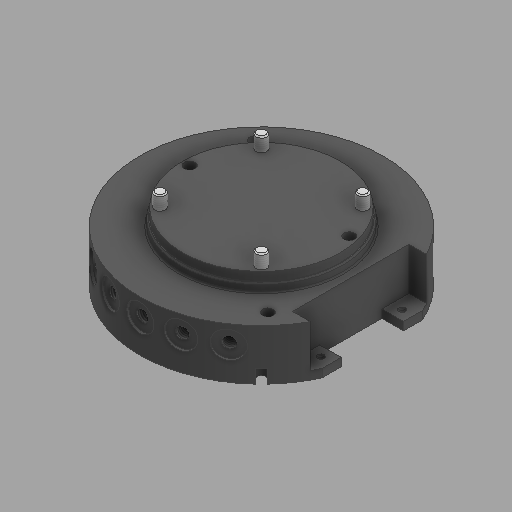
# Autodesk Inventor part: SCHUNK-SWK-020, 0
Saved by Autodesk Inventor 2025.3 (Build 293356000, 356)
## iProperties
Category: PARTsolutions
Company: SCHUNK
Created: 2026-08-11
Part Number: SCHUNK-SWK-020, 0
Material: Generic
Catalog Web Link: www.3dfindit.com
Description: SWS-Quick change system
Vendor: SCHUNK
Document SubType Name: Modeling
Designer: psAdmin
Manufacturer: SCHUNK
Mass: 134.925 g
Surface Area: 279.959 cm^2
Volume: 134.925 cm^3
Density: 1 g/cm^3
Appearance: PSOLRGB-84-84-84
PSOL_IDENT_0: {$CADENAS_DATA/23d-libs/schunk/greifsysteme/roboterzubehoer/wechseln/schnellwechselsystem/sws/sws.pr
PSOL_IDENT_1: j},171 {VTYP=3D},{NB=SCHUNK-SWK-020, 0},{LINA=SCHUNK-SWK-020},{NN=SWS},{DATE=18.09.2025 11:03:47},{G
PSOL_IDENT_2: EOMDATE=08.07.2025 10:05:37},{VERSION=},{LINEID=70},{WBVAR=SIP},{WBNUMERIC=}  {NB=SCHUNK-SWK-020, 0}
PSOL_IDENT_3: ,{LINA=SCHUNK-SWK-020},{KT=7},{TYP=SWK-020},{ABDECK=1.000},{TYP1=5.000},{NHS=0.000},{ONLINE=Zur Prod
PSOL_IDENT_4: uktseite},{SIP=ohne},{TYPSIP='ohne','ohne','SWK-020-SIP','0302325 - SWK-020-SIP'},{NBSIP=0},{SWSI=1.
PSOL_IDENT_5: 000},{PARTSERVER=0.000},{V=7.000},{SWKH=1.000},{L1=86.000},{L2=23.000},{L3=0.000},{L3A=0.000},{L4=0.
PSOL_IDENT_6: 000},{L4A=0.000},{L5=0.000},{L5A=0.000},{L6=14.000},{L6A=3.200},{L7=5.700},{L8=0.500},{L9=30.000},{L
PSOL_IDENT_7: 10=43.000},{L11=0.000},{B1=18.700},{B2=3.000},{B3=12.000},{B3A=0.000},{B4=8.300},{B4I=38.600},{B5=32
PSOL_IDENT_8: .000},{B5A=0.000},{B6=33.000},{B7=26.500},{B8=0.000},{B9=0.000},{B9A=0.000},{B9B=0.000},{B9C=0.000},
PSOL_IDENT_9: {B10=58.400},{B11=4.000},{B12=41.000},{B13=3.000},{B14=0.000},{A=13.600},{D1=60.000},{D2=90.000},{D3=
PSOL_IDENT_10: 53.000},{D4=4.000},{D5=0.000},{D6=4.000},{W1=0.000},{W1A=0.000},{W2=17.000},{W3=45.000},{W4=45.000},
PSOL_IDENT_11: {W5=15.000},{W6=0.000},{W7=0.000},{W8=0.000},{T1=4.000},{T2=7.000},{T2A=0.000},{T3=7.000},{T4=0.000}
PSOL_IDENT_12: ,{T5=0.000},{T6=16.000},{T7=0.000},{M1=M4},{NDR1=4.000},{KDR1=3.141},{M2=M5},{NDR2=5.000},{KDR2=4.13
PSOL_IDENT_13: 4},{M2A=-},{NDR2A=0.000},{KDR2A=0.000},{M3=M5},{NDR3=5.000},{KDR3=4.134},{M4=-},{NDR4=0.000},{KDR4=0
PSOL_IDENT_14: .000},{M5=M3},{NDR5=3.000},{KDR5=2.459},{M6=-},{NDR6=0.000},{KDR6=0.000},{B=38.800},{C=7.050},{D=9.5
PSOL_IDENT_15: 00},{E=10.000},{F=9.000},{G=4.000},{H=1.000},{R=2.000},{YX=33.000},{SWSI1=5.000},{CUSTOM=SWK-020_SCH
PSOL_IDENT_16: UNK},{SCHSWS=2.000},{G1=0.000},{PY1=0.000},{PX1=0.000},{BG=020}
NB: SCHUNK-SWK-020, 0
NN: SWS
NT: Quick change system
NBSYN: SCHUNK-$TYP., $NBSIP.
LINA: SCHUNK-SWK-020
CATALOG: SCHUNK
TYP: SWK-020
NHS: 0
ONLINE: To the product page
SIP: without
CUSTOM: SWK-020_SCHUNK
SUPPLIER: SCHUNK
ARTICLENO: SCHUNK-SWK-020, 0
BOMINFO: SCHUNK-SWK-020
CREATOR: CADENAS GmbH
Title: SCHUNK-SWK-020
Author: Cadenas PARTsolutions
Comments: Quick change system
Autodesk Inventor part; units mm, degrees
sketch "Sketch_1" plane through (0, 0, 0) normal (0, 0, 1) x (1, 0, 0)
  line L0 (0, -0.2) -> (0, 17.8)
  line L1 (0, 17.8) -> (19, 17.8)
  line L2 (19, 17.8) -> (19, 21.7)
  line L3 (19, 21.7) -> (21.5, 21.7)
  line L4 (21.5, 21.7) -> (21.5, 20.7)
  line L5 (21.5, 20.7) -> (23.75, 20.7)
  line L6 (23.75, 20.7) -> (23.75, 21.7)
  line L7 (23.75, 21.7) -> (29.5, 21.7)
  line L8 (29.5, 21.7) -> (30, 21.2)
  line L9 (30, 21.2) -> (30, 19.2)
  arc A0 (30, 19.2) -> (30.5, 18.7) centre (30.5, 19.2) ccw
  line L10 (30.5, 18.7) -> (45, 18.7)
  line L11 (45, 18.7) -> (45, 0)
  line L12 (45, 0) -> (31, 0)
  line L13 (31, 0) -> (31, -0.2)
  line L14 (31, -0.2) -> (19.4, -0.2)
  line L15 (19.4, -0.2) -> (19.4, -11.6)
  line L16 (19.4, -11.6) -> (17.4, -13.6)
  line L17 (17.4, -13.6) -> (13.27, -13.6)
  line L18 (13.27, -13.6) -> (13.27, -0.2)
  line L19 (13.27, -0.2) -> (0, -0.2)
  line L20 (0, -0.2) -> (0, 17.8)
  constraints: 42 end point, 2 point on circle, 1 centre point
revolve "Revolution1" add sketch "Sketch_1" angle 360 about axis through (0, -0.2, 0) along (0, 1, 0)
sketch "Sketch_5" plane through (0, -7.1, 0) normal (0, 1, 0) x (1, 0, 0)
  line L0 (-15.6, 4.8) -> (-15.6, -4.8)
  arc A0 (-15.6, 4.8) -> (-15.6, -4.8) centre (-15.6, 0) ccw
  line L1 (-15.6, 4.8) -> (-15.6, -4.8)
  constraints: 4 end point, 2 point on circle, 1 centre point
revolve "Revolution2" cut sketch "Sketch_5" angle 360 about axis through (-15.6, -7.1, -4.8) along (0, 0, -1)
sketch "Sketch_36" plane through (0, -7.1, 0) normal (0, 1, 0) x (1, 0, 0)
  line L0 (-15.6, 4.8) -> (-15.6, -4.8)
  arc A0 (-15.6, 4.8) -> (-15.6, -4.8) centre (-15.6, 0) ccw
  line L1 (-15.6, 4.8) -> (-15.6, -4.8)
  constraints: 4 end point, 2 point on circle, 1 centre point
revolve "Revolution3" add sketch "Sketch_36" angle 360 about axis through (-15.6, -7.1, -4.8) along (0, 0, -1)
sketch "Sketch_3" plane through (0, -7.1, 0) normal (0, 1, 0) x (1, 0, 0)
  line L0 (4.8, 15.6) -> (-4.8, 15.6)
  arc A0 (4.8, 15.6) -> (-4.8, 15.6) centre (0, 15.6) ccw
  line L1 (4.8, 15.6) -> (-4.8, 15.6)
  constraints: 4 end point, 2 point on circle, 1 centre point
revolve "Revolution4" cut sketch "Sketch_3" angle 360 about axis through (4.8, -7.1, -15.6) along (1, 0, 0)
sketch "Sketch_6" plane through (0, -7.1, 0) normal (0, 1, 0) x (1, 0, 0)
  line L0 (4.8, 15.6) -> (-4.8, 15.6)
  arc A0 (4.8, 15.6) -> (-4.8, 15.6) centre (0, 15.6) ccw
  line L1 (4.8, 15.6) -> (-4.8, 15.6)
  constraints: 4 end point, 2 point on circle, 1 centre point
revolve "Revolution5" add sketch "Sketch_6" angle 360 about axis through (4.8, -7.1, -15.6) along (1, 0, 0)
sketch "Sketch_4" plane through (0, -7.1, 0) normal (0, 1, 0) x (1, 0, 0)
  line L0 (-4.8, -15.6) -> (4.8, -15.6)
  arc A0 (-4.8, -15.6) -> (4.8, -15.6) centre (0, -15.6) ccw
  line L1 (-4.8, -15.6) -> (4.8, -15.6)
  constraints: 4 end point, 2 point on circle, 1 centre point
revolve "Revolution6" cut sketch "Sketch_4" angle 360 about axis through (-4.8, -7.1, 15.6) along (-1, 0, 0)
sketch "Sketch_7" plane through (0, -7.1, 0) normal (0, 1, 0) x (1, 0, 0)
  line L0 (-4.8, -15.6) -> (4.8, -15.6)
  arc A0 (-4.8, -15.6) -> (4.8, -15.6) centre (0, -15.6) ccw
  line L1 (-4.8, -15.6) -> (4.8, -15.6)
  constraints: 4 end point, 2 point on circle, 1 centre point
revolve "Revolution7" add sketch "Sketch_7" angle 360 about axis through (-4.8, -7.1, 15.6) along (-1, 0, 0)
sketch "Sketch_2" plane through (0, -7.1, 0) normal (0, 1, 0) x (1, 0, 0)
  line L0 (15.6, -4.8) -> (15.6, 4.8)
  arc A0 (15.6, -4.8) -> (15.6, 4.8) centre (15.6, 0) ccw
  line L1 (15.6, -4.8) -> (15.6, 4.8)
  constraints: 4 end point, 2 point on circle, 1 centre point
revolve "Revolution8" cut sketch "Sketch_2" angle 360 about axis through (15.6, -7.1, 4.8) along (0, 0, 1)
sketch "Sketch_8" plane through (0, -7.1, 0) normal (0, 1, 0) x (1, 0, 0)
  line L0 (15.6, -4.8) -> (15.6, 4.8)
  arc A0 (15.6, -4.8) -> (15.6, 4.8) centre (15.6, 0) ccw
  line L1 (15.6, -4.8) -> (15.6, 4.8)
  constraints: 4 end point, 2 point on circle, 1 centre point
revolve "Revolution9" add sketch "Sketch_8" angle 360 about axis through (15.6, -7.1, 4.8) along (0, 0, 1)
sketch "Sketch_12" plane through (0, 0, 18.7383) normal (0, 0, 1) x (1, 0, 0)
  line L0 (18.7383, -0.2) -> (18.7383, 0.7)
  line L1 (18.7383, 0.7) -> (22.6883, 0.7)
  line L2 (22.6883, 0.7) -> (23.5883, -0.2)
  line L3 (23.5883, -0.2) -> (18.7383, -0.2)
  line L4 (18.7383, -0.2) -> (18.7383, 0.7)
  constraints: 10 end point
revolve "Revolution10" cut sketch "Sketch_12" angle 360 about axis through (18.7383, -0.2, 18.7383) along (0, 1, 0)
sketch "Sketch_13" plane through (0, 0, 18.7383) normal (0, 0, 1) x (1, 0, 0)
  line L0 (-18.7383, -0.2) -> (-18.7383, 0.7)
  line L1 (-18.7383, 0.7) -> (-14.7883, 0.7)
  line L2 (-14.7883, 0.7) -> (-13.8883, -0.2)
  line L3 (-13.8883, -0.2) -> (-18.7383, -0.2)
  line L4 (-18.7383, -0.2) -> (-18.7383, 0.7)
  constraints: 10 end point
revolve "Revolution11" cut sketch "Sketch_13" angle 360 about axis through (-18.7383, -0.2, 18.7383) along (0, 1, 0)
sketch "Sketch_14" plane through (0, 0, -18.7383) normal (0, 0, 1) x (1, 0, 0)
  line L0 (18.7383, -0.2) -> (18.7383, 0.7)
  line L1 (18.7383, 0.7) -> (22.6883, 0.7)
  line L2 (22.6883, 0.7) -> (23.5883, -0.2)
  line L3 (23.5883, -0.2) -> (18.7383, -0.2)
  line L4 (18.7383, -0.2) -> (18.7383, 0.7)
  constraints: 10 end point
revolve "Revolution12" cut sketch "Sketch_14" angle 360 about axis through (18.7383, -0.2, -18.7383) along (0, 1, 0)
sketch "Sketch_15" plane through (0, 0, -18.7383) normal (0, 0, 1) x (1, 0, 0)
  line L0 (-18.7383, -0.2) -> (-18.7383, 0.7)
  line L1 (-18.7383, 0.7) -> (-14.7883, 0.7)
  line L2 (-14.7883, 0.7) -> (-13.8883, -0.2)
  line L3 (-13.8883, -0.2) -> (-18.7383, -0.2)
  line L4 (-18.7383, -0.2) -> (-18.7383, 0.7)
  constraints: 10 end point
revolve "Revolution13" cut sketch "Sketch_15" angle 360 about axis through (-18.7383, -0.2, -18.7383) along (0, 1, 0)
sketch "Sketch_10" plane through (0, 0, 0) normal (0, 0, 1) x (1, 0, 0)
  line L0 (0, 21.7) -> (0, 24.9)
  line L1 (0, 24.9) -> (29.2, 24.9)
  line L2 (29.2, 24.9) -> (29.2, 21.7)
  line L3 (29.2, 21.7) -> (0, 21.7)
  line L4 (0, 21.7) -> (0, 24.9)
  constraints: 10 end point
revolve "Revolution14" add sketch "Sketch_10" angle 360 about axis through (0, 21.7, 0) along (0, -1, 0)
sketch "Sketch_16" plane through (0, 0, 18.7383) normal (0, 0, 1) x (1, 0, 0)
  line L0 (18.7383, 21.7) -> (18.7383, 30)
  line L1 (18.7383, 30) -> (20.3088, 30)
  line L2 (20.3088, 30) -> (20.7383, 29.5705)
  line L3 (20.7383, 29.5705) -> (20.7383, 21.7)
  line L4 (20.7383, 21.7) -> (18.7383, 21.7)
  line L5 (18.7383, 21.7) -> (18.7383, 30)
  constraints: 12 end point
revolve "Revolution15" add sketch "Sketch_16" angle 360 about axis through (18.7383, 21.7, 18.7383) along (0, 1, 0)
thread "Thread1" size "M4x0.7" class "6g" standard "ISO Metric profile" length 7.8705
sketch "Sketch_17" plane through (0, 0, 18.7383) normal (0, 0, 1) x (1, 0, 0)
  line L0 (-18.7383, 21.7) -> (-18.7383, 30)
  line L1 (-18.7383, 30) -> (-17.1678, 30)
  line L2 (-17.1678, 30) -> (-16.7383, 29.5705)
  line L3 (-16.7383, 29.5705) -> (-16.7383, 21.7)
  line L4 (-16.7383, 21.7) -> (-18.7383, 21.7)
  line L5 (-18.7383, 21.7) -> (-18.7383, 30)
  constraints: 12 end point
revolve "Revolution16" add sketch "Sketch_17" angle 360 about axis through (-18.7383, 21.7, 18.7383) along (0, 1, 0)
thread "Thread2" size "M4x0.7" class "6g" standard "ISO Metric profile" length 7.8705
sketch "Sketch_18" plane through (0, 0, -18.7383) normal (0, 0, 1) x (1, 0, 0)
  line L0 (18.7383, 21.7) -> (18.7383, 30)
  line L1 (18.7383, 30) -> (20.3088, 30)
  line L2 (20.3088, 30) -> (20.7383, 29.5705)
  line L3 (20.7383, 29.5705) -> (20.7383, 21.7)
  line L4 (20.7383, 21.7) -> (18.7383, 21.7)
  line L5 (18.7383, 21.7) -> (18.7383, 30)
  constraints: 12 end point
revolve "Revolution17" add sketch "Sketch_18" angle 360 about axis through (18.7383, 21.7, -18.7383) along (0, 1, 0)
thread "Thread3" size "M4x0.7" class "6g" standard "ISO Metric profile" length 7.8705
sketch "Sketch_19" plane through (0, 0, -18.7383) normal (0, 0, 1) x (1, 0, 0)
  line L0 (-18.7383, 21.7) -> (-18.7383, 30)
  line L1 (-18.7383, 30) -> (-17.1678, 30)
  line L2 (-17.1678, 30) -> (-16.7383, 29.5705)
  line L3 (-16.7383, 29.5705) -> (-16.7383, 21.7)
  line L4 (-16.7383, 21.7) -> (-18.7383, 21.7)
  line L5 (-18.7383, 21.7) -> (-18.7383, 30)
  constraints: 12 end point
revolve "Revolution18" add sketch "Sketch_19" angle 360 about axis through (-18.7383, 21.7, -18.7383) along (0, 1, 0)
thread "Thread4" size "M4x0.7" class "6g" standard "ISO Metric profile" length 7.8705
sketch "Sketch_20" plane through (45, 0, 0) normal (1, 0, 0) x (0, 0, -1)
  line L0 (-21.5, 2.999) -> (-11.5, 2.999)
  line L1 (-11.5, 2.999) -> (-11.5, -0.001)
  line L2 (-11.5, -0.001) -> (11.5, -0.001)
  line L3 (11.5, -0.001) -> (11.5, 2.999)
  line L4 (11.5, 2.999) -> (21.5, 2.999)
  line L5 (21.5, 2.999) -> (21.5, 18.701)
  line L6 (21.5, 18.701) -> (-21.5, 18.701)
  line L7 (-21.5, 18.701) -> (-21.5, 2.999)
  constraints: 16 end point
extrude "Extrusion1" cut sketch "Sketch_20" against normal blind 12
sketch "Sketch20" plane through (33, 0, -11.5) normal (0, -1, 0) x (1, 0, 0)
  point P0 (-67.9051, 0.8284)
hole "Hole1" at (-34.9051, 0, -10.6716) direction (0, 1, 0) diameter 3 depth 7.05 tip angle 120 countersink diameter 8 countersink angle 90
sketch "Sketch21" plane through (33, 0, -11.5) normal (0, -1, 0) x (1, 0, 0)
  point P0 (-67.9051, 22.1716)
hole "Hole2" at (-34.9051, 0, 10.6716) direction (0, 1, 0) diameter 3 depth 7.05 tip angle 120 countersink diameter 8 countersink angle 90
sketch "Sketch22" plane through (33, 0, -11.5) normal (0, -1, 0) x (1, 0, 0)
  point P0 (-63.2599, -8.9105)
hole "Hole3" at (-30.2599, 0, -20.4105) direction (0, 1, 0) diameter 3 depth 7.05 tip angle 120 countersink diameter 8 countersink angle 90
sketch "Sketch23" plane through (33, 0, -11.5) normal (0, -1, 0) x (1, 0, 0)
  point P0 (-63.2599, 31.9105)
hole "Hole4" at (-30.2599, 0, 20.4105) direction (0, 1, 0) diameter 3 depth 7.05 tip angle 120 countersink diameter 8 countersink angle 90
sketch "Sketch24" plane through (33, 0, -11.5) normal (0, -1, 0) x (1, 0, 0)
  point P0 (-22.3284, 46.4051)
hole "Hole5" at (10.6716, 0, 34.9051) direction (0, 1, 0) diameter 3 depth 7.05 tip angle 120 countersink diameter 8 countersink angle 90
sketch "Sketch25" plane through (33, 0, -11.5) normal (0, -1, 0) x (1, 0, 0)
  point P0 (-43.6716, 46.4051)
hole "Hole6" at (-10.6716, 0, 34.9051) direction (0, 1, 0) diameter 3 depth 7.05 tip angle 120 countersink diameter 8 countersink angle 90
sketch "Sketch26" plane through (33, 0, -11.5) normal (0, -1, 0) x (1, 0, 0)
  point P0 (-12.5895, 41.7599)
hole "Hole7" at (20.4105, 0, 30.2599) direction (0, 1, 0) diameter 3 depth 7.05 tip angle 120 countersink diameter 8 countersink angle 90
sketch "Sketch27" plane through (33, 0, -11.5) normal (0, -1, 0) x (1, 0, 0)
  point P0 (-53.4105, 41.7599)
hole "Hole8" at (-20.4105, 0, 30.2599) direction (0, 1, 0) diameter 3 depth 7.05 tip angle 120 countersink diameter 8 countersink angle 90
sketch "Sketch28" plane through (33, 0, -11.5) normal (0, -1, 0) x (1, 0, 0)
  point P0 (-12.5895, -18.7599)
hole "Hole9" at (20.4105, 0, -30.2599) direction (0, 1, 0) diameter 3 depth 7.05 tip angle 120 countersink diameter 8 countersink angle 90
sketch "Sketch29" plane through (33, 0, -11.5) normal (0, -1, 0) x (1, 0, 0)
  point P0 (-53.4105, -18.7599)
hole "Hole10" at (-20.4105, 0, -30.2599) direction (0, 1, 0) diameter 3 depth 7.05 tip angle 120 countersink diameter 8 countersink angle 90
sketch "Sketch30" plane through (33, 0, -11.5) normal (0, -1, 0) x (1, 0, 0)
  point P0 (-22.3284, -23.4051)
hole "Hole11" at (10.6716, 0, -34.9051) direction (0, 1, 0) diameter 3 depth 7.05 tip angle 120 countersink diameter 8 countersink angle 90
sketch "Sketch31" plane through (33, 0, -11.5) normal (0, -1, 0) x (1, 0, 0)
  point P0 (-43.6716, -23.4051)
hole "Hole12" at (-10.6716, 0, -34.9051) direction (0, 1, 0) diameter 3 depth 7.05 tip angle 120 countersink diameter 8 countersink angle 90
sketch "Sketch_33" plane through (0, 0, 0) normal (1, 0, 0) x (0, 1, 0)
  line L0 (-9.199, -26) -> (-0.199, -26)
  line L1 (-0.199, -26) -> (-0.199, -28)
  line L2 (-0.199, -28) -> (-1.199, -28)
  line L3 (-1.199, -28) -> (-8.323, -27.1095)
  arc A0 (-9.199, -26.1172) -> (-8.323, -27.1095) centre (-8.199, -26.1172) ccw
  line L4 (-9.199, -26.1172) -> (-9.199, -26)
  line L5 (-9.199, -26) -> (-0.199, -26)
  constraints: 12 end point, 2 point on circle, 1 centre point
revolve "Revolution19" add sketch "Sketch_33" angle 360 about axis through (0, -9.199, -26) along (0, 1, 0)
sketch "Sketch_37" plane through (0, 0, -6.8587) normal (0, 0, 1) x (1, 0, 0)
  line L0 (-25.597, 3.3) -> (-25.597, -0.2)
  line L1 (-25.597, -0.2) -> (-28.597, -0.2)
  line L2 (-28.597, -0.2) -> (-28.597, 3.3)
  line L3 (-28.597, 3.3) -> (-25.597, 3.3)
  line L4 (-25.597, 3.3) -> (-25.597, -0.2)
  constraints: 10 end point
revolve "Revolution20" cut sketch "Sketch_37" angle 360 about axis through (-25.597, 3.3, -6.8587) along (0, -1, 0)
sketch "Sketch_38" plane through (0, 0, 6.8587) normal (0, 0, 1) x (1, 0, 0)
  line L0 (25.597, 3.3) -> (25.597, -0.2)
  line L1 (25.597, -0.2) -> (22.597, -0.2)
  line L2 (22.597, -0.2) -> (22.597, 3.3)
  line L3 (22.597, 3.3) -> (25.597, 3.3)
  line L4 (25.597, 3.3) -> (25.597, -0.2)
  constraints: 10 end point
revolve "Revolution21" cut sketch "Sketch_38" angle 360 about axis through (25.597, 3.3, 6.8587) along (0, -1, 0)
sketch "Sketch_39" plane through (0, -0.001, 0) normal (0, 1, 0) x (1, 0, 0)
  line L0 (41, -25) -> (46, -25)
  line L1 (46, -25) -> (46, 25)
  line L2 (46, 25) -> (41, 25)
  line L3 (41, 25) -> (41, -25)
  constraints: 8 end point
extrude "Extrusion2" cut sketch "Sketch_39" along normal blind 4
sketch "Sketch_40" plane through (37, 0, 0) normal (1, 0, 0) x (0, 0, -1)
  line L0 (15, 0) -> (15, 3)
  line L1 (15, 3) -> (16.2295, 3)
  line L2 (16.2295, 3) -> (16.2295, 0)
  line L3 (16.2295, 0) -> (15, 0)
  line L4 (15, 0) -> (15, 3)
  constraints: 10 end point
revolve "Revolution22" cut sketch "Sketch_40" angle 360 about axis through (37, 0, -15) along (0, 1, 0)
thread "Thread5" size "M3x0.5" class "6H" standard "ISO Metric profile" length 3
sketch "Sketch_41" plane through (37, 0, 0) normal (1, 0, 0) x (0, 0, -1)
  line L0 (-15, 0) -> (-15, 3)
  line L1 (-15, 3) -> (-13.7705, 3)
  line L2 (-13.7705, 3) -> (-13.7705, 0)
  line L3 (-13.7705, 0) -> (-15, 0)
  line L4 (-15, 0) -> (-15, 3)
  constraints: 10 end point
revolve "Revolution23" cut sketch "Sketch_41" angle 360 about axis through (37, 0, 15) along (0, 1, 0)
thread "Thread6" size "M3x0.5" class "6H" standard "ISO Metric profile" length 3
sketch "Sketch_42" plane through (0, -0.001, 0) normal (0, 1, 0) x (1, 0, 0)
  arc A0 (31.1127, -28.9914) -> (28.9914, -31.1127) centre (30.052, -30.052) ccw
  line L0 (28.9914, -31.1127) -> (30.7591, -32.8805)
  line L1 (30.7591, -32.8805) -> (32.8805, -30.7591)
  line L2 (32.8805, -30.7591) -> (31.1127, -28.9914)
  constraints: 6 end point, 2 point on circle, 1 centre point
extrude "Extrusion3" cut sketch "Sketch_42" along normal blind 5
sketch "Sketch_43" plane through (0, -0.001, 0) normal (0, 1, 0) x (1, 0, 0)
  line L0 (-32.8805, -30.7591) -> (-30.7591, -32.8805)
  line L1 (-30.7591, -32.8805) -> (-28.9914, -31.1127)
  arc A0 (-28.9914, -31.1127) -> (-31.1127, -28.9914) centre (-30.052, -30.052) ccw
  line L2 (-31.1127, -28.9914) -> (-32.8805, -30.7591)
  constraints: 6 end point, 2 point on circle, 1 centre point
extrude "Extrusion4" cut sketch "Sketch_43" along normal blind 5
sketch "Sketch_44" plane through (0, 12, 0) normal (0, 1, 0) x (1, 0, 0)
  line L0 (13.1567, -43.0337) -> (9.5186, -31.1341)
  line L1 (9.5186, -31.1341) -> (11.8442, -31.671)
  line L2 (11.8442, -31.671) -> (14.841, -41.4731)
  line L3 (14.841, -41.4731) -> (17.6459, -40.6156)
  line L4 (17.6459, -40.6156) -> (17.9383, -41.5719)
  line L5 (17.9383, -41.5719) -> (13.1567, -43.0337)
  line L6 (13.1567, -43.0337) -> (9.5186, -31.1341)
  constraints: 14 end point
revolve "Revolution24" cut sketch "Sketch_44" angle 360 about axis through (13.1567, 12, 43.0337) along (-0.2923717, 0, -0.9563048)
thread "Thread7" size "M5x0.8" class "6H" standard "ISO Metric profile" length 7
sketch "Sketch_45" plane through (0, 12, 0) normal (0, 1, 0) x (1, 0, 0)
  line L0 (25.1637, -37.3067) -> (18.2054, -26.9907)
  line L1 (18.2054, -26.9907) -> (20.5864, -26.8242)
  line L2 (20.5864, -26.8242) -> (26.3181, -35.3218)
  line L3 (26.3181, -35.3218) -> (28.7497, -33.6817)
  line L4 (28.7497, -33.6817) -> (29.3089, -34.5107)
  line L5 (29.3089, -34.5107) -> (25.1637, -37.3067)
  line L6 (25.1637, -37.3067) -> (18.2054, -26.9907)
  constraints: 14 end point
revolve "Revolution25" cut sketch "Sketch_45" angle 360 about axis through (25.1637, 12, 37.3067) along (-0.5591929, 0, -0.8290376)
thread "Thread8" size "M5x0.8" class "6H" standard "ISO Metric profile" length 7
sketch "Sketch_46" plane through (0, 12, 0) normal (0, 1, 0) x (1, 0, 0)
  line L0 (-13.1567, -43.0337) -> (-9.5186, -31.1341)
  line L1 (-9.5186, -31.1341) -> (-7.8909, -32.8796)
  line L2 (-7.8909, -32.8796) -> (-10.8877, -42.6817)
  line L3 (-10.8877, -42.6817) -> (-8.0828, -43.5393)
  line L4 (-8.0828, -43.5393) -> (-8.3752, -44.4956)
  line L5 (-8.3752, -44.4956) -> (-13.1567, -43.0337)
  line L6 (-13.1567, -43.0337) -> (-9.5186, -31.1341)
  constraints: 14 end point
revolve "Revolution26" cut sketch "Sketch_46" angle 360 about axis through (-13.1567, 12, 43.0337) along (0.2923717, 0, -0.9563048)
thread "Thread9" size "M5x0.8" class "6H" standard "ISO Metric profile" length 7
sketch "Sketch_47" plane through (0, 12, 0) normal (0, 1, 0) x (1, 0, 0)
  line L0 (-25.1637, -37.3067) -> (-18.2054, -26.9907)
  line L1 (-18.2054, -26.9907) -> (-17.1591, -29.1359)
  line L2 (-17.1591, -29.1359) -> (-22.8909, -37.6335)
  line L3 (-22.8909, -37.6335) -> (-20.4593, -39.2736)
  line L4 (-20.4593, -39.2736) -> (-21.0185, -40.1027)
  line L5 (-21.0185, -40.1027) -> (-25.1637, -37.3067)
  line L6 (-25.1637, -37.3067) -> (-18.2054, -26.9907)
  constraints: 14 end point
revolve "Revolution27" cut sketch "Sketch_47" angle 360 about axis through (-25.1637, 12, 37.3067) along (0.5591929, 0, -0.8290376)
thread "Thread10" size "M5x0.8" class "6H" standard "ISO Metric profile" length 7
sketch "Sketch_48" plane through (0, 12, 0) normal (0, 1, 0) x (1, 0, 0)
  line L0 (-43.0337, -13.1567) -> (-31.1341, -9.5186)
  line L1 (-31.1341, -9.5186) -> (-31.671, -11.8442)
  line L2 (-31.671, -11.8442) -> (-41.4731, -14.841)
  line L3 (-41.4731, -14.841) -> (-40.6156, -17.6459)
  line L4 (-40.6156, -17.6459) -> (-41.5719, -17.9383)
  line L5 (-41.5719, -17.9383) -> (-43.0337, -13.1567)
  line L6 (-43.0337, -13.1567) -> (-31.1341, -9.5186)
  constraints: 14 end point
revolve "Revolution28" cut sketch "Sketch_48" angle 360 about axis through (-43.0337, 12, 13.1567) along (0.9563048, 0, -0.2923717)
thread "Thread11" size "M5x0.8" class "6H" standard "ISO Metric profile" length 7
sketch "Sketch_49" plane through (0, 12, 0) normal (0, 1, 0) x (1, 0, 0)
  line L0 (-37.3067, -25.1637) -> (-26.9907, -18.2054)
  line L1 (-26.9907, -18.2054) -> (-26.8242, -20.5864)
  line L2 (-26.8242, -20.5864) -> (-35.3218, -26.3181)
  line L3 (-35.3218, -26.3181) -> (-33.6817, -28.7497)
  line L4 (-33.6817, -28.7497) -> (-34.5107, -29.3089)
  line L5 (-34.5107, -29.3089) -> (-37.3067, -25.1637)
  line L6 (-37.3067, -25.1637) -> (-26.9907, -18.2054)
  constraints: 14 end point
revolve "Revolution29" cut sketch "Sketch_49" angle 360 about axis through (-37.3067, 12, 25.1637) along (0.8290376, 0, -0.5591929)
thread "Thread12" size "M5x0.8" class "6H" standard "ISO Metric profile" length 7
sketch "Sketch_50" plane through (0, 12, 0) normal (0, 1, 0) x (1, 0, 0)
  line L0 (-43.0337, 13.1567) -> (-31.1341, 9.5186)
  line L1 (-31.1341, 9.5186) -> (-32.8796, 7.8909)
  line L2 (-32.8796, 7.8909) -> (-42.6817, 10.8877)
  line L3 (-42.6817, 10.8877) -> (-43.5393, 8.0828)
  line L4 (-43.5393, 8.0828) -> (-44.4956, 8.3752)
  line L5 (-44.4956, 8.3752) -> (-43.0337, 13.1567)
  line L6 (-43.0337, 13.1567) -> (-31.1341, 9.5186)
  constraints: 14 end point
revolve "Revolution30" cut sketch "Sketch_50" angle 360 about axis through (-43.0337, 12, -13.1567) along (0.9563048, 0, 0.2923717)
thread "Thread13" size "M5x0.8" class "6H" standard "ISO Metric profile" length 7
sketch "Sketch_51" plane through (0, 12, 0) normal (0, 1, 0) x (1, 0, 0)
  line L0 (-37.3067, 25.1637) -> (-26.9907, 18.2054)
  line L1 (-26.9907, 18.2054) -> (-29.1359, 17.1591)
  line L2 (-29.1359, 17.1591) -> (-37.6335, 22.8909)
  line L3 (-37.6335, 22.8909) -> (-39.2736, 20.4593)
  line L4 (-39.2736, 20.4593) -> (-40.1027, 21.0185)
  line L5 (-40.1027, 21.0185) -> (-37.3067, 25.1637)
  line L6 (-37.3067, 25.1637) -> (-26.9907, 18.2054)
  constraints: 14 end point
revolve "Revolution31" cut sketch "Sketch_51" angle 360 about axis through (-37.3067, 12, -25.1637) along (0.8290376, 0, 0.5591929)
thread "Thread14" size "M5x0.8" class "6H" standard "ISO Metric profile" length 7
sketch "Sketch_52" plane through (0, 12, 0) normal (0, 1, 0) x (1, 0, 0)
  line L0 (13.1567, 43.0337) -> (9.5186, 31.1341)
  line L1 (9.5186, 31.1341) -> (7.8909, 32.8796)
  line L2 (7.8909, 32.8796) -> (10.8877, 42.6817)
  line L3 (10.8877, 42.6817) -> (8.0828, 43.5393)
  line L4 (8.0828, 43.5393) -> (8.3752, 44.4956)
  line L5 (8.3752, 44.4956) -> (13.1567, 43.0337)
  line L6 (13.1567, 43.0337) -> (9.5186, 31.1341)
  constraints: 14 end point
revolve "Revolution32" cut sketch "Sketch_52" angle 360 about axis through (13.1567, 12, -43.0337) along (-0.2923717, 0, 0.9563048)
thread "Thread15" size "M5x0.8" class "6H" standard "ISO Metric profile" length 7
sketch "Sketch_53" plane through (0, 12, 0) normal (0, 1, 0) x (1, 0, 0)
  line L0 (25.1637, 37.3067) -> (18.2054, 26.9907)
  line L1 (18.2054, 26.9907) -> (17.1591, 29.1359)
  line L2 (17.1591, 29.1359) -> (22.8909, 37.6335)
  line L3 (22.8909, 37.6335) -> (20.4593, 39.2736)
  line L4 (20.4593, 39.2736) -> (21.0185, 40.1027)
  line L5 (21.0185, 40.1027) -> (25.1637, 37.3067)
  line L6 (25.1637, 37.3067) -> (18.2054, 26.9907)
  constraints: 14 end point
revolve "Revolution33" cut sketch "Sketch_53" angle 360 about axis through (25.1637, 12, -37.3067) along (-0.5591929, 0, 0.8290376)
thread "Thread16" size "M5x0.8" class "6H" standard "ISO Metric profile" length 7
sketch "Sketch_54" plane through (0, 12, 0) normal (0, 1, 0) x (1, 0, 0)
  line L0 (-13.1567, 43.0337) -> (-9.5186, 31.1341)
  line L1 (-9.5186, 31.1341) -> (-11.8442, 31.671)
  line L2 (-11.8442, 31.671) -> (-14.841, 41.4731)
  line L3 (-14.841, 41.4731) -> (-17.6459, 40.6156)
  line L4 (-17.6459, 40.6156) -> (-17.9383, 41.5719)
  line L5 (-17.9383, 41.5719) -> (-13.1567, 43.0337)
  line L6 (-13.1567, 43.0337) -> (-9.5186, 31.1341)
  constraints: 14 end point
revolve "Revolution34" cut sketch "Sketch_54" angle 360 about axis through (-13.1567, 12, -43.0337) along (0.2923717, 0, 0.9563048)
thread "Thread17" size "M5x0.8" class "6H" standard "ISO Metric profile" length 7
sketch "Sketch_55" plane through (0, 12, 0) normal (0, 1, 0) x (1, 0, 0)
  line L0 (-25.1637, 37.3067) -> (-18.2054, 26.9907)
  line L1 (-18.2054, 26.9907) -> (-20.5864, 26.8242)
  line L2 (-20.5864, 26.8242) -> (-26.3181, 35.3218)
  line L3 (-26.3181, 35.3218) -> (-28.7497, 33.6817)
  line L4 (-28.7497, 33.6817) -> (-29.3089, 34.5107)
  line L5 (-29.3089, 34.5107) -> (-25.1637, 37.3067)
  line L6 (-25.1637, 37.3067) -> (-18.2054, 26.9907)
  constraints: 14 end point
revolve "Revolution35" cut sketch "Sketch_55" angle 360 about axis through (-25.1637, 12, -37.3067) along (0.5591929, 0, 0.8290376)
thread "Thread18" size "M5x0.8" class "6H" standard "ISO Metric profile" length 7
sketch "Sketch_56" plane through (0, 12, 0) normal (0, 1, 0) x (1, 0, 0)
  line L0 (0, 45) -> (0, 32.5566)
  line L1 (0, 32.5566) -> (-2.067, 33.75)
  line L2 (-2.067, 33.75) -> (-2.067, 44)
  line L3 (-2.067, 44) -> (-5, 44)
  line L4 (-5, 44) -> (-5, 45)
  line L5 (-5, 45) -> (0, 45)
  line L6 (0, 45) -> (0, 32.5566)
  constraints: 14 end point
revolve "Revolution36" cut sketch "Sketch_56" angle 360 about axis through (0, 12, -45) along (0, 0, 1)
thread "Thread19" size "M5x0.8" class "6H" standard "ISO Metric profile" length 7
sketch "Sketch_57" plane through (0, 12, 0) normal (0, 1, 0) x (1, 0, 0)
  line L0 (0, -45) -> (0, -32.5566)
  line L1 (0, -32.5566) -> (2.067, -33.75)
  line L2 (2.067, -33.75) -> (2.067, -44)
  line L3 (2.067, -44) -> (5, -44)
  line L4 (5, -44) -> (5, -45)
  line L5 (5, -45) -> (0, -45)
  line L6 (0, -45) -> (0, -32.5566)
  constraints: 14 end point
revolve "Revolution37" cut sketch "Sketch_57" angle 360 about axis through (0, 12, 45) along (0, 0, -1)
thread "Thread20" size "M5x0.8" class "6H" standard "ISO Metric profile" length 7
sketch "Sketch_58" plane through (18.7383, 0.7, 18.7383) normal (0, -1, 0) x (1, 0, 0)
  line L0 (-1.25, -0.7217) -> (0, -1.4434)
  line L1 (0, -1.4434) -> (1.25, -0.7217)
  line L2 (1.25, -0.7217) -> (1.25, 0.7217)
  line L3 (1.25, 0.7217) -> (0, 1.4434)
  line L4 (0, 1.4434) -> (-1.25, 0.7217)
  line L5 (-1.25, 0.7217) -> (-1.25, -0.7217)
  constraints: 12 end point
extrude "Extrusion5" cut sketch "Sketch_58" against normal blind 1.8
sketch "Sketch_59" plane through (-18.7383, 0.7, 18.7383) normal (0, -1, 0) x (1, 0, 0)
  line L0 (-1.25, -0.7217) -> (0, -1.4434)
  line L1 (0, -1.4434) -> (1.25, -0.7217)
  line L2 (1.25, -0.7217) -> (1.25, 0.7217)
  line L3 (1.25, 0.7217) -> (0, 1.4434)
  line L4 (0, 1.4434) -> (-1.25, 0.7217)
  line L5 (-1.25, 0.7217) -> (-1.25, -0.7217)
  constraints: 12 end point
extrude "Extrusion6" cut sketch "Sketch_59" against normal blind 1.8
sketch "Sketch_60" plane through (-18.7383, 0.7, -18.7383) normal (0, -1, 0) x (1, 0, 0)
  line L0 (-1.25, -0.7217) -> (0, -1.4434)
  line L1 (0, -1.4434) -> (1.25, -0.7217)
  line L2 (1.25, -0.7217) -> (1.25, 0.7217)
  line L3 (1.25, 0.7217) -> (0, 1.4434)
  line L4 (0, 1.4434) -> (-1.25, 0.7217)
  line L5 (-1.25, 0.7217) -> (-1.25, -0.7217)
  constraints: 12 end point
extrude "Extrusion7" cut sketch "Sketch_60" against normal blind 1.8
sketch "Sketch_61" plane through (18.7383, 0.7, -18.7383) normal (0, -1, 0) x (1, 0, 0)
  line L0 (-1.25, -0.7217) -> (0, -1.4434)
  line L1 (0, -1.4434) -> (1.25, -0.7217)
  line L2 (1.25, -0.7217) -> (1.25, 0.7217)
  line L3 (1.25, 0.7217) -> (0, 1.4434)
  line L4 (0, 1.4434) -> (-1.25, 0.7217)
  line L5 (-1.25, 0.7217) -> (-1.25, -0.7217)
  constraints: 12 end point
extrude "Extrusion8" cut sketch "Sketch_61" against normal blind 1.8
sketch "Sketch_35" plane through (-26.5, 0, 0) normal (1, 0, 0) x (0, 0, -1)
  line L0 (0, 24.902) -> (0, 17.7)
  line L1 (0, 17.7) -> (-2, 17.7)
  line L2 (-2, 17.7) -> (-2, 24.902)
  line L3 (-2, 24.902) -> (0, 24.902)
  line L4 (0, 24.902) -> (0, 17.7)
  constraints: 10 end point
revolve "Revolution38" cut sketch "Sketch_35" angle 360 about axis through (-26.5, 24.902, 0) along (0, -1, 0)
sketch "zentrierung_SKETCH_1" plane through (2.266, 0.199, 51.9011) normal (1, 0, 0) x (0, 0, -1)
  line L0 (26, -9.199) -> (26, -0.199)
  line L1 (26, -0.199) -> (28, -0.199)
  line L2 (28, -0.199) -> (28, -1.199)
  line L3 (28, -1.199) -> (27.1095, -8.323)
  arc A0 (26.1172, -9.199) -> (27.1095, -8.323) centre (26.1172, -8.199) ccw
  line L4 (26.1172, -9.199) -> (26, -9.199)
  line L5 (26, -9.199) -> (26, -0.199)
  constraints: 12 end point, 2 point on circle, 1 centre point
revolve "Revolution39" add sketch "zentrierung_SKETCH_1" angle 360 about axis through (2.266, -9, 25.9011) along (0, 1, 0)
sketch "Sketch60" plane through (0, 24.9, 0) normal (0, 1, 0) x (1, 0, 0)
  point P0 (25.597, 6.8587)
hole "Hole13" at (25.597, 24.9, -6.8587) direction (0, -1, 0) diameter 4 depth 7.202
sketch "Sketch_9" plane through (0, 0, 0) normal (1, 0, 0) x (0, 1, 0)
  line L0 (-13.4, 0) -> (0, 0)
  line L1 (0, 0) -> (0, -13.27)
  line L2 (0, -13.27) -> (-13.4, -13.27)
  line L3 (-13.4, -13.27) -> (-13.4, 0)
  line L4 (-13.4, 0) -> (0, 0)
  constraints: 10 end point
revolve "Revolution40" add sketch "Sketch_9" angle 360 about axis through (0, -13.4, 0) along (0, -1, 0)
sketch "Sketch62" plane through (33, 18.7, -21.5) normal (0, 1, 0) x (1, 0, 0)
  point P0 (-4.25, -47.85)
hole "Hole14" at (28.75, 18.7, 26.35) direction (0, -1, 0) diameter 4 depth 6
pattern_linear "Rectangular Pattern1" count 2 spacing 77.9971 along (-0.7372074, 0, -0.6756666) of "Hole14"
ref_plane "apl_XY" through (0, 24.9, 0) normal (0, 1, 0) x (1, 0, 0)
ref_plane "apl_YZ" through (0, 24.9, 0) normal (1, 0, 0) x (0, 0, -1)
ref_plane "apl_ZX" through (0, 24.9, 0) normal (0, 0, -1) x (0, 1, 0)
ref_plane "sa_XY" through (-43.0337, 12, 13.1567) normal (0.9563048, 0, -0.2923717) x (-0.2923717, 0, -0.9563048)
ref_plane "sa_YZ" through (-43.0337, 12, 13.1567) normal (-0.2923717, 0, -0.9563048) x (0, 1, 0)
ref_plane "sa_ZX" through (-43.0337, 12, 13.1567) normal (0, 1, 0) x (0.9563048, 0, -0.2923717)
ref_plane "sa1_XY" through (-37.3067, 12, 25.1637) normal (0.8290376, 0, -0.5591929) x (-0.5591929, 0, -0.8290376)
ref_plane "sa1_YZ" through (-37.3067, 12, 25.1637) normal (-0.5591929, 0, -0.8290376) x (0, 1, 0)
ref_plane "sa1_ZX" through (-37.3067, 12, 25.1637) normal (0, 1, 0) x (0.8290376, 0, -0.5591929)
ref_plane "sa10_XY" through (-13.1567, 12, -43.0337) normal (0.2923717, 0, 0.9563048) x (0.9563048, 0, -0.2923717)
ref_plane "sa10_YZ" through (-13.1567, 12, -43.0337) normal (0.9563048, 0, -0.2923717) x (0, 1, 0)
ref_plane "sa10_ZX" through (-13.1567, 12, -43.0337) normal (0, 1, 0) x (0.2923717, 0, 0.9563048)
ref_plane "sa11_XY" through (0, 12, -45) normal (0, 0, 1) x (1, 0, 0)
ref_plane "sa11_YZ" through (0, 12, -45) normal (1, 0, 0) x (0, 1, 0)
ref_plane "sa11_ZX" through (0, 12, -45) normal (0, 1, 0) x (0, 0, 1)
ref_plane "sa12_XY" through (13.1567, 12, -43.0337) normal (-0.2923717, 0, 0.9563048) x (-0.9563048, 0, -0.2923717)
ref_plane "sa12_YZ" through (13.1567, 12, -43.0337) normal (-0.9563048, 0, -0.2923717) x (0, -1, 0)
ref_plane "sa12_ZX" through (13.1567, 12, -43.0337) normal (0, -1, 0) x (-0.2923717, 0, 0.9563048)
ref_plane "sa13_XY" through (25.1637, 12, -37.3067) normal (-0.5591929, 0, 0.8290376) x (0.8290376, 0, 0.5591929)
ref_plane "sa13_YZ" through (25.1637, 12, -37.3067) normal (0.8290376, 0, 0.5591929) x (0, 1, 0)
ref_plane "sa13_ZX" through (25.1637, 12, -37.3067) normal (0, 1, 0) x (-0.5591929, 0, 0.8290376)
ref_plane "sa2_XY" through (-25.1637, 12, 37.3067) normal (0.5591929, 0, -0.8290376) x (0.8290376, 0, 0.5591929)
ref_plane "sa2_YZ" through (-25.1637, 12, 37.3067) normal (0.8290376, 0, 0.5591929) x (0, -1, 0)
ref_plane "sa2_ZX" through (-25.1637, 12, 37.3067) normal (0, -1, 0) x (0.5591929, 0, -0.8290376)
ref_plane "sa3_XY" through (-13.1567, 12, 43.0337) normal (0.2923717, 0, -0.9563048) x (0.9563048, 0, 0.2923717)
ref_plane "sa3_YZ" through (-13.1567, 12, 43.0337) normal (0.9563048, 0, 0.2923717) x (0, -1, 0)
ref_plane "sa3_ZX" through (-13.1567, 12, 43.0337) normal (0, -1, 0) x (0.2923717, 0, -0.9563048)
ref_plane "sa4_XY" through (0, 12, 45) normal (0, 0, -1) x (1, 0, 0)
ref_plane "sa4_YZ" through (0, 12, 45) normal (1, 0, 0) x (0, -1, 0)
ref_plane "sa4_ZX" through (0, 12, 45) normal (0, -1, 0) x (0, 0, -1)
ref_plane "sa5_XY" through (13.1567, 12, 43.0337) normal (-0.2923717, 0, -0.9563048) x (0.9563048, 0, -0.2923717)
ref_plane "sa5_YZ" through (13.1567, 12, 43.0337) normal (0.9563048, 0, -0.2923717) x (0, -1, 0)
ref_plane "sa5_ZX" through (13.1567, 12, 43.0337) normal (0, -1, 0) x (-0.2923717, 0, -0.9563048)
ref_plane "sa6_XY" through (25.1637, 12, 37.3067) normal (-0.5591929, 0, -0.8290376) x (0.8290376, 0, -0.5591929)
ref_plane "sa6_YZ" through (25.1637, 12, 37.3067) normal (0.8290376, 0, -0.5591929) x (0, -1, 0)
ref_plane "sa6_ZX" through (25.1637, 12, 37.3067) normal (0, -1, 0) x (-0.5591929, 0, -0.8290376)
ref_plane "sa7_XY" through (-43.0337, 12, -13.1567) normal (0.9563048, 0, 0.2923717) x (0.2923717, 0, -0.9563048)
ref_plane "sa7_YZ" through (-43.0337, 12, -13.1567) normal (0.2923717, 0, -0.9563048) x (0, 1, 0)
ref_plane "sa7_ZX" through (-43.0337, 12, -13.1567) normal (0, 1, 0) x (0.9563048, 0, 0.2923717)
ref_plane "sa8_XY" through (-37.3067, 12, -25.1637) normal (0.8290376, 0, 0.5591929) x (0.5591929, 0, -0.8290376)
ref_plane "sa8_YZ" through (-37.3067, 12, -25.1637) normal (0.5591929, 0, -0.8290376) x (0, 1, 0)
ref_plane "sa8_ZX" through (-37.3067, 12, -25.1637) normal (0, 1, 0) x (0.8290376, 0, 0.5591929)
ref_plane "sa9_XY" through (-25.1637, 12, -37.3067) normal (0.5591929, 0, 0.8290376) x (-0.8290376, 0, 0.5591929)
ref_plane "sa9_YZ" through (-25.1637, 12, -37.3067) normal (-0.8290376, 0, 0.5591929) x (0, -1, 0)
ref_plane "sa9_ZX" through (-25.1637, 12, -37.3067) normal (0, -1, 0) x (0.5591929, 0, 0.8290376)
ref_plane "sip_XY" through (0, 21.7, 0) normal (0, 1, 0) x (1, 0, 0)
ref_plane "sip_YZ" through (0, 21.7, 0) normal (1, 0, 0) x (0, 0, -1)
ref_plane "sip_ZX" through (0, 21.7, 0) normal (0, 0, -1) x (0, 1, 0)
ref_plane "ste_swk_XY" through (37, 3, 15) normal (-1, 0, 0) x (0, 0, -1)
ref_plane "ste_swk_YZ" through (37, 3, 15) normal (0, 0, -1) x (0, -1, 0)
ref_plane "ste_swk_ZX" through (37, 3, 15) normal (0, -1, 0) x (-1, 0, 0)
ref_plane "stecker_swk_XY" through (37, 3, 15) normal (1, 0, 0) x (0, 0, -1)
ref_plane "stecker_swk_YZ" through (37, 3, 15) normal (0, 0, -1) x (0, 1, 0)
ref_plane "stecker_swk_ZX" through (37, 3, 15) normal (0, 1, 0) x (1, 0, 0)
ref_plane "swo_XY" through (37, 3, 15) normal (0, 1, 0) x (1, 0, 0)
ref_plane "swo_YZ" through (37, 3, 15) normal (1, 0, 0) x (0, 0, -1)
ref_plane "swo_ZX" through (37, 3, 15) normal (0, 0, -1) x (0, 1, 0)
ref_plane "sws_XY" through (0, 0, 0) normal (0, 1, 0) x (1, 0, 0)
ref_plane "sws_YZ" through (0, 0, 0) normal (1, 0, 0) x (0, 0, -1)
ref_plane "sws_ZX" through (0, 0, 0) normal (0, 0, -1) x (0, 1, 0)
ref_plane "swsi_XY" through (0, 18.7, 0) normal (0, 1, 0) x (1, 0, 0)
ref_plane "swsi_YZ" through (0, 18.7, 0) normal (1, 0, 0) x (0, 0, -1)
ref_plane "swsi_ZX" through (0, 18.7, 0) normal (0, 0, -1) x (0, 1, 0)
body "Solid1"
